Autodesk Fusion 360 part; units mm, degrees
(part 2 of 4)
sketch "Switch_Latch" plane through (0, 0, 0) normal (0, 0, -1) x (1, 0, 0) in component "Plate_Left"
  line L0 (111.75, 39.3) -> (111.75, 25.3)
  line L1 (111.75, 25.3) -> (97.75, 25.3)
  line L2 (97.75, 25.3) -> (97.75, 39.3)
  line L3 (97.75, 39.3) -> (111.75, 39.3)
  line L4 (92.7, 55.69) -> (92.7, 41.69)
  line L5 (92.7, 41.69) -> (78.7, 41.69)
  line L6 (78.7, 41.69) -> (78.7, 55.69)
  line L7 (78.7, 55.69) -> (92.7, 55.69)
  line L8 (59.65, 78.7) -> (59.65, 92.7)
  line L9 (59.65, 92.7) -> (73.65, 92.7)
  line L10 (73.65, 92.7) -> (73.65, 78.7)
  line L11 (73.65, 78.7) -> (59.65, 78.7)
  line L12 (59.65, 16.5) -> (73.65, 16.5)
  line L13 (73.65, 16.5) -> (73.65, 2.5)
  line L14 (73.65, 2.5) -> (59.65, 2.5)
  line L15 (59.65, 2.5) -> (59.65, 16.5)
  line L16 (40.6, 79.79) -> (40.6, 93.79)
  line L17 (40.6, 93.79) -> (54.6, 93.79)
  line L18 (54.6, 93.79) -> (54.6, 79.79)
  line L19 (54.6, 79.79) -> (40.6, 79.79)
  line L20 (21.55, 21.21) -> (35.55, 21.21)
  line L21 (35.55, 21.21) -> (35.55, 7.21)
  line L22 (35.55, 7.21) -> (21.55, 7.21)
  line L23 (21.55, 7.21) -> (21.55, 21.21)
  line L24 (2.5, 79.5) -> (16.5, 79.5)
  line L25 (16.5, 79.5) -> (16.5, 65.5)
  line L26 (16.5, 65.5) -> (2.5, 65.5)
  line L27 (2.5, 65.5) -> (2.5, 79.5)
  line L28 (2.5, 98.55) -> (16.5, 98.55)
  line L29 (16.5, 98.55) -> (16.5, 84.55)
  line L30 (16.5, 84.55) -> (2.5, 84.55)
  line L31 (2.5, 84.55) -> (2.5, 98.55)
  line L32 (2.5, 60.45) -> (16.5, 60.45)
  line L33 (16.5, 60.45) -> (16.5, 46.45)
  line L34 (16.5, 46.45) -> (2.5, 46.45)
  line L35 (2.5, 46.45) -> (2.5, 60.45)
  line L36 (35.55, 40.26) -> (35.55, 26.26)
  line L37 (35.55, 26.26) -> (21.55, 26.26)
  line L38 (21.55, 26.26) -> (21.55, 40.26)
  line L39 (21.55, 40.26) -> (35.55, 40.26)
  line L40 (54.6, 55.69) -> (54.6, 41.69)
  line L41 (54.6, 41.69) -> (40.6, 41.69)
  line L42 (40.6, 41.69) -> (40.6, 55.69)
  line L43 (40.6, 55.69) -> (54.6, 55.69)
  line L44 (73.65, 35.55) -> (73.65, 21.55)
  line L45 (73.65, 21.55) -> (59.65, 21.55)
  line L46 (59.65, 21.55) -> (59.65, 35.55)
  line L47 (59.65, 35.55) -> (73.65, 35.55)
  line L48 (90.1617, 83.0445) -> (84.4545, 95.8284)
  line L49 (84.4545, 95.8284) -> (97.2384, 101.5355)
  line L50 (97.2384, 101.5355) -> (102.9456, 88.7516)
  line L51 (102.9456, 88.7516) -> (90.1617, 83.0445)
  line L52 (92.7, 36.64) -> (92.7, 22.64)
  line L53 (92.7, 22.64) -> (78.7, 22.64)
  line L54 (78.7, 22.64) -> (78.7, 36.64)
  line L55 (78.7, 36.64) -> (92.7, 36.64)
  line L56 (111.75, 58.35) -> (111.75, 44.35)
  line L57 (111.75, 44.35) -> (97.75, 44.35)
  line L58 (97.75, 44.35) -> (97.75, 58.35)
  line L59 (97.75, 58.35) -> (111.75, 58.35)
  line L60 (97.75, 20.25) -> (111.75, 20.25)
  line L61 (111.75, 20.25) -> (111.75, 6.25)
  line L62 (111.75, 6.25) -> (97.75, 6.25)
  line L63 (97.75, 6.25) -> (97.75, 20.25)
  line L64 (78.7, 60.74) -> (78.7, 74.74)
  line L65 (78.7, 74.74) -> (92.7, 74.74)
  line L66 (92.7, 74.74) -> (92.7, 60.74)
  line L67 (92.7, 60.74) -> (78.7, 60.74)
  line L68 (59.65, 59.65) -> (59.65, 73.65)
  line L69 (59.65, 73.65) -> (73.65, 73.65)
  line L70 (73.65, 73.65) -> (73.65, 59.65)
  line L71 (73.65, 59.65) -> (59.65, 59.65)
  line L72 (40.6, 17.59) -> (54.6, 17.59)
  line L73 (54.6, 17.59) -> (54.6, 3.59)
  line L74 (54.6, 3.59) -> (40.6, 3.59)
  line L75 (40.6, 3.59) -> (40.6, 17.59)
  line L76 (40.6, 60.74) -> (40.6, 74.74)
  line L77 (40.6, 74.74) -> (54.6, 74.74)
  line L78 (54.6, 74.74) -> (54.6, 60.74)
  line L79 (54.6, 60.74) -> (40.6, 60.74)
  line L80 (16.5, 22.35) -> (16.5, 8.35)
  line L81 (16.5, 8.35) -> (2.5, 8.35)
  line L82 (2.5, 8.35) -> (2.5, 22.35)
  line L83 (2.5, 22.35) -> (16.5, 22.35)
  line L84 (21.55, 64.36) -> (21.55, 78.36)
  line L85 (21.55, 78.36) -> (35.55, 78.36)
  line L86 (35.55, 78.36) -> (35.55, 64.36)
  line L87 (35.55, 64.36) -> (21.55, 64.36)
  line L88 (21.55, 83.41) -> (21.55, 97.41)
  line L89 (21.55, 97.41) -> (35.55, 97.41)
  line L90 (35.55, 97.41) -> (35.55, 83.41)
  line L91 (35.55, 83.41) -> (21.55, 83.41)
  line L92 (2.5, 27.4) -> (2.5, 41.4)
  line L93 (2.5, 41.4) -> (16.5, 41.4)
  line L94 (16.5, 41.4) -> (16.5, 27.4)
  line L95 (16.5, 27.4) -> (2.5, 27.4)
  line L96 (35.55, 59.31) -> (35.55, 45.31)
  line L97 (35.55, 45.31) -> (21.55, 45.31)
  line L98 (21.55, 45.31) -> (21.55, 59.31)
  line L99 (21.55, 59.31) -> (35.55, 59.31)
  line L100 (54.6, 36.64) -> (54.6, 22.64)
  line L101 (54.6, 22.64) -> (40.6, 22.64)
  line L102 (40.6, 22.64) -> (40.6, 36.64)
  line L103 (40.6, 36.64) -> (54.6, 36.64)
  line L104 (73.65, 54.6) -> (73.65, 40.6)
  line L105 (73.65, 40.6) -> (59.65, 40.6)
  line L106 (59.65, 40.6) -> (59.65, 54.6)
  line L107 (59.65, 54.6) -> (73.65, 54.6)
  line L108 (112.7117, 92.7045) -> (107.0045, 105.4884)
  line L109 (107.0045, 105.4884) -> (119.7884, 111.1955)
  line L110 (119.7884, 111.1955) -> (125.4956, 98.4116)
  line L111 (125.4956, 98.4116) -> (112.7117, 92.7045)
  line L112 (78.7, 17.59) -> (92.7, 17.59)
  line L113 (92.7, 17.59) -> (92.7, 3.59)
  line L114 (92.7, 3.59) -> (78.7, 3.59)
  line L115 (78.7, 3.59) -> (78.7, 17.59)
  line L116 (97.75, 63.4) -> (97.75, 77.4)
  line L117 (97.75, 77.4) -> (111.75, 77.4)
  line L118 (111.75, 77.4) -> (111.75, 63.4)
  line L119 (111.75, 63.4) -> (97.75, 63.4)
  line L120 (119.3123, 118.9999) -> (83.6581, 103.172)
  arc A0 (82.8467, 103) -> (83.6581, 103.172) centre (82.8467, 105) ccw
  line L121 (82.8467, 103) -> (0, 103)
  arc A1 (0, 103) -> (-6, 97) centre (0, 97) ccw
  line L122 (-6, 97) -> (-6, 6.0028)
  arc A2 (-6, 6.0028) -> (0, 0.0028) centre (0, 6.0028) ccw
  line L123 (0, 0.0028) -> (135.25, 0.0028)
  arc A3 (135.25, 0.0028) -> (141.25, 6.0028) centre (135.25, 6.0028) ccw
  line L124 (141.25, 6.0028) -> (141.25, 113.172)
  arc A4 (141.25, 113.172) -> (135.25, 119.172) centre (135.25, 113.172) ccw
  line L125 (135.25, 119.172) -> (120.1238, 119.172)
  arc A5 (120.1238, 119.172) -> (119.3123, 118.9999) centre (120.1238, 117.172) ccw
  line L126 (107.75, 20.25) -> (101.75, 20.25)
  line L127 (101.75, 20.25) -> (101.75, 21.75)
  line L128 (101.75, 21.75) -> (107.75, 21.75)
  line L129 (107.75, 21.75) -> (107.75, 20.25)
  line L130 (107.75, 4.75) -> (101.75, 4.75)
  line L131 (101.75, 4.75) -> (101.75, 6.25)
  line L132 (101.75, 6.25) -> (107.75, 6.25)
  line L133 (107.75, 6.25) -> (107.75, 4.75)
  line L134 (101.75, 25.3) -> (107.75, 25.3)
  line L135 (107.75, 25.3) -> (107.75, 23.8)
  line L136 (107.75, 23.8) -> (101.75, 23.8)
  line L137 (101.75, 23.8) -> (101.75, 25.3)
  line L138 (107.75, 39.3) -> (101.75, 39.3)
  line L139 (101.75, 39.3) -> (101.75, 40.8)
  line L140 (107.75, 40.8) -> (107.75, 39.3)
  line L141 (101.75, 40.8) -> (107.75, 40.8)
  line L142 (101.75, 44.35) -> (107.75, 44.35)
  line L143 (101.75, 58.35) -> (101.75, 59.85)
  line L144 (107.75, 44.35) -> (107.75, 42.85)
  line L145 (107.75, 59.85) -> (107.75, 58.35)
  line L146 (101.75, 42.85) -> (101.75, 44.35)
  line L147 (107.75, 42.85) -> (101.75, 42.85)
  line L148 (107.75, 58.35) -> (101.75, 58.35)
  line L149 (101.75, 59.85) -> (107.75, 59.85)
  line L150 (88.7, 21.14) -> (82.7, 21.14)
  line L151 (88.7, 3.59) -> (88.7, 2.09)
  line L152 (82.7, 2.09) -> (82.7, 3.59)
  line L153 (88.7, 17.59) -> (82.7, 17.59)
  line L154 (88.7, 2.09) -> (82.7, 2.09)
  line L155 (88.7, 22.64) -> (88.7, 21.14)
  line L156 (82.7, 21.14) -> (82.7, 22.64)
  line L157 (88.7, 38.14) -> (88.7, 36.64)
  line L158 (82.7, 19.09) -> (88.7, 19.09)
  line L159 (82.7, 36.64) -> (82.7, 38.14)
  line L160 (82.7, 22.64) -> (88.7, 22.64)
  line L161 (88.7, 36.64) -> (82.7, 36.64)
  line L162 (82.7, 17.59) -> (82.7, 19.09)
  line L163 (82.7, 38.14) -> (88.7, 38.14)
  line L164 (88.7, 19.09) -> (88.7, 17.59)
  line L165 (82.7, 3.59) -> (88.7, 3.59)
  line L166 (88.7, 41.69) -> (88.7, 40.19)
  line L167 (101.75, 61.9) -> (101.75, 63.4)
  line L168 (88.7, 57.19) -> (88.7, 55.69)
  line L169 (82.7, 57.19) -> (88.7, 57.19)
  line L170 (82.7, 55.69) -> (82.7, 57.19)
  line L171 (88.7, 55.69) -> (82.7, 55.69)
  line L172 (101.75, 78.9) -> (107.75, 78.9)
  line L173 (107.75, 78.9) -> (107.75, 77.4)
  line L174 (88.7, 40.19) -> (82.7, 40.19)
  line L175 (82.7, 40.19) -> (82.7, 41.69)
  line L176 (107.75, 61.9) -> (101.75, 61.9)
  line L177 (101.75, 77.4) -> (101.75, 78.9)
  line L178 (107.75, 77.4) -> (101.75, 77.4)
  line L179 (101.75, 63.4) -> (107.75, 63.4)
  line L180 (82.7, 41.69) -> (88.7, 41.69)
  line L181 (107.75, 63.4) -> (107.75, 61.9)
  line L182 (88.7, 60.74) -> (88.7, 59.24)
  line L183 (88.7, 59.24) -> (82.7, 59.24)
  line L184 (82.7, 60.74) -> (88.7, 60.74)
  line L185 (88.7, 74.74) -> (82.7, 74.74)
  line L186 (82.7, 76.24) -> (88.7, 76.24)
  line L187 (82.7, 59.24) -> (82.7, 60.74)
  line L188 (88.7, 76.24) -> (88.7, 74.74)
  line L189 (82.7, 74.74) -> (82.7, 76.24)
  line L190 (69.65, 77.2) -> (63.65, 77.2)
  line L191 (69.65, 73.65) -> (63.65, 73.65)
  line L192 (63.65, 59.65) -> (69.65, 59.65)
  line L193 (63.65, 78.7) -> (69.65, 78.7)
  line L194 (69.65, 58.15) -> (63.65, 58.15)
  line L195 (63.65, 92.7) -> (63.65, 94.2)
  line L196 (69.65, 92.7) -> (63.65, 92.7)
  line L197 (63.65, 77.2) -> (63.65, 78.7)
  line L198 (69.65, 75.15) -> (69.65, 73.65)
  line L199 (63.65, 73.65) -> (63.65, 75.15)
  line L200 (63.65, 75.15) -> (69.65, 75.15)
  line L201 (69.65, 78.7) -> (69.65, 77.2)
  line L202 (63.65, 94.2) -> (69.65, 94.2)
  line L203 (69.65, 59.65) -> (69.65, 58.15)
  line L204 (63.65, 58.15) -> (63.65, 59.65)
  line L205 (69.65, 94.2) -> (69.65, 92.7)
  line L206 (50.6, 95.29) -> (50.6, 93.79)
  line L207 (31.55, 98.91) -> (31.55, 97.41)
  line L208 (50.6, 79.79) -> (50.6, 78.29)
  line L209 (44.6, 38.14) -> (50.6, 38.14)
  line L210 (44.6, 93.79) -> (44.6, 95.29)
  line L211 (25.55, 83.41) -> (31.55, 83.41)
  line L212 (50.6, 21.14) -> (44.6, 21.14)
  line L213 (31.55, 81.91) -> (25.55, 81.91)
  line L214 (50.6, 36.64) -> (44.6, 36.64)
  line L215 (44.6, 21.14) -> (44.6, 22.64)
  line L216 (6.5, 98.55) -> (6.5, 100.05)
  line L217 (12.5, 100.05) -> (12.5, 98.55)
  line L218 (44.6, 36.64) -> (44.6, 38.14)
  line L219 (44.6, 79.79) -> (50.6, 79.79)
  line L220 (44.6, 22.64) -> (50.6, 22.64)
  line L221 (50.6, 93.79) -> (44.6, 93.79)
  line L222 (44.6, 78.29) -> (44.6, 79.79)
  line L223 (6.5, 100.05) -> (12.5, 100.05)
  line L224 (50.6, 78.29) -> (44.6, 78.29)
  line L225 (12.5, 83.05) -> (6.5, 83.05)
  line L226 (50.6, 22.64) -> (50.6, 21.14)
  line L227 (12.5, 84.55) -> (12.5, 83.05)
  line L228 (6.5, 84.55) -> (12.5, 84.55)
  line L229 (44.6, 95.29) -> (50.6, 95.29)
  line L230 (6.5, 83.05) -> (6.5, 84.55)
  line L231 (50.6, 38.14) -> (50.6, 36.64)
  line L232 (31.55, 97.41) -> (25.55, 97.41)
  line L233 (12.5, 98.55) -> (6.5, 98.55)
  line L234 (31.55, 83.41) -> (31.55, 81.91)
  line L235 (25.55, 98.91) -> (31.55, 98.91)
  line L236 (25.55, 81.91) -> (25.55, 83.41)
  line L237 (25.55, 97.41) -> (25.55, 98.91)
  line L238 (31.55, 62.86) -> (25.55, 62.86)
  line L239 (69.65, 35.55) -> (63.65, 35.55)
  line L240 (50.6, 41.69) -> (50.6, 40.19)
  line L241 (50.6, 40.19) -> (44.6, 40.19)
  line L242 (69.65, 20.05) -> (63.65, 20.05)
  line L243 (63.65, 40.6) -> (69.65, 40.6)
  line L244 (31.55, 59.31) -> (25.55, 59.31)
  line L245 (6.5, 65.5) -> (12.5, 65.5)
  line L246 (25.55, 45.31) -> (31.55, 45.31)
  line L247 (12.5, 64) -> (6.5, 64)
  line L248 (69.65, 54.6) -> (63.65, 54.6)
  line L249 (69.65, 40.6) -> (69.65, 39.1)
  line L250 (12.5, 46.45) -> (12.5, 44.95)
  line L251 (6.5, 79.5) -> (6.5, 81)
  line L252 (31.55, 64.36) -> (31.55, 62.86)
  line L253 (44.6, 40.19) -> (44.6, 41.69)
  line L254 (12.5, 60.45) -> (6.5, 60.45)
  line L255 (31.55, 78.36) -> (25.55, 78.36)
  line L256 (44.6, 76.24) -> (50.6, 76.24)
  line L257 (50.6, 55.69) -> (44.6, 55.69)
  line L258 (63.65, 20.05) -> (63.65, 21.55)
  line L259 (50.6, 74.74) -> (44.6, 74.74)
  line L260 (44.6, 41.69) -> (50.6, 41.69)
  line L261 (63.65, 56.1) -> (69.65, 56.1)
  line L262 (6.5, 64) -> (6.5, 65.5)
  line L263 (69.65, 56.1) -> (69.65, 54.6)
  line L264 (12.5, 81) -> (12.5, 79.5)
  line L265 (63.65, 21.55) -> (69.65, 21.55)
  line L266 (44.6, 59.24) -> (44.6, 60.74)
  line L267 (50.6, 60.74) -> (50.6, 59.24)
  line L268 (6.5, 44.95) -> (6.5, 46.45)
  line L269 (69.65, 39.1) -> (63.65, 39.1)
  line L270 (44.6, 60.74) -> (50.6, 60.74)
  line L271 (31.55, 43.81) -> (25.55, 43.81)
  line L272 (12.5, 61.95) -> (12.5, 60.45)
  line L273 (25.55, 43.81) -> (25.55, 45.31)
  line L274 (69.65, 21.55) -> (69.65, 20.05)
  line L275 (25.55, 64.36) -> (31.55, 64.36)
  line L276 (12.5, 79.5) -> (6.5, 79.5)
  line L277 (6.5, 46.45) -> (12.5, 46.45)
  line L278 (6.5, 60.45) -> (6.5, 61.95)
  line L279 (12.5, 44.95) -> (6.5, 44.95)
  line L280 (63.65, 39.1) -> (63.65, 40.6)
  line L281 (25.55, 62.86) -> (25.55, 64.36)
  line L282 (12.5, 65.5) -> (12.5, 64)
  line L283 (6.5, 61.95) -> (12.5, 61.95)
  line L284 (50.6, 76.24) -> (50.6, 74.74)
  line L285 (25.55, 59.31) -> (25.55, 60.81)
  line L286 (44.6, 74.74) -> (44.6, 76.24)
  line L287 (44.6, 55.69) -> (44.6, 57.19)
  line L288 (63.65, 54.6) -> (63.65, 56.1)
  line L289 (31.55, 45.31) -> (31.55, 43.81)
  line L290 (6.5, 81) -> (12.5, 81)
  line L291 (50.6, 59.24) -> (44.6, 59.24)
  line L292 (63.65, 37.05) -> (69.65, 37.05)
  line L293 (25.55, 60.81) -> (31.55, 60.81)
  line L294 (69.65, 37.05) -> (69.65, 35.55)
  line L295 (25.55, 79.86) -> (31.55, 79.86)
  line L296 (31.55, 79.86) -> (31.55, 78.36)
  line L297 (50.6, 57.19) -> (50.6, 55.69)
  line L298 (44.6, 57.19) -> (50.6, 57.19)
  line L299 (25.55, 78.36) -> (25.55, 79.86)
  line L300 (63.65, 35.55) -> (63.65, 37.05)
  line L301 (31.55, 60.81) -> (31.55, 59.31)
  line L302 (12.5, 41.4) -> (6.5, 41.4)
  line L303 (12.5, 25.9) -> (6.5, 25.9)
  line L304 (25.55, 26.26) -> (31.55, 26.26)
  line L305 (69.65, 16.5) -> (63.65, 16.5)
  line L306 (25.55, 7.21) -> (31.55, 7.21)
  line L307 (63.65, 2.5) -> (69.65, 2.5)
  line L308 (31.55, 5.71) -> (25.55, 5.71)
  line L309 (31.55, 40.26) -> (25.55, 40.26)
  line L310 (31.55, 26.26) -> (31.55, 24.76)
  line L311 (50.6, 3.59) -> (50.6, 2.09)
  line L312 (25.55, 21.21) -> (25.55, 22.71)
  line L313 (50.6, 17.59) -> (44.6, 17.59)
  line L314 (6.5, 23.85) -> (12.5, 23.85)
  line L315 (6.5, 25.9) -> (6.5, 27.4)
  line L316 (12.5, 22.35) -> (6.5, 22.35)
  line L317 (25.55, 41.76) -> (31.55, 41.76)
  line L318 (25.55, 5.71) -> (25.55, 7.21)
  line L319 (31.55, 41.76) -> (31.55, 40.26)
  line L320 (31.55, 22.71) -> (31.55, 21.21)
  line L321 (6.5, 27.4) -> (12.5, 27.4)
  line L322 (6.5, 6.85) -> (6.5, 8.35)
  line L323 (12.5, 8.35) -> (12.5, 6.85)
  line L324 (44.6, 2.09) -> (44.6, 3.59)
  line L325 (31.55, 24.76) -> (25.55, 24.76)
  line L326 (6.5, 8.35) -> (12.5, 8.35)
  line L327 (69.65, 1) -> (63.65, 1)
  line L328 (50.6, 19.09) -> (50.6, 17.59)
  line L329 (63.65, 1) -> (63.65, 2.5)
  line L330 (12.5, 27.4) -> (12.5, 25.9)
  line L331 (31.55, 21.21) -> (25.55, 21.21)
  line L332 (44.6, 3.59) -> (50.6, 3.59)
  line L333 (44.6, 17.59) -> (44.6, 19.09)
  line L334 (50.6, 2.09) -> (44.6, 2.09)
  line L335 (25.55, 24.76) -> (25.55, 26.26)
  line L336 (31.55, 7.21) -> (31.55, 5.71)
  line L337 (44.6, 19.09) -> (50.6, 19.09)
  line L338 (12.5, 23.85) -> (12.5, 22.35)
  line L339 (63.65, 16.5) -> (63.65, 18)
  line L340 (6.5, 22.35) -> (6.5, 23.85)
  line L341 (25.55, 40.26) -> (25.55, 41.76)
  line L342 (69.65, 2.5) -> (69.65, 1)
  line L343 (25.55, 22.71) -> (31.55, 22.71)
  line L344 (12.5, 6.85) -> (6.5, 6.85)
  line L345 (6.5, 42.9) -> (12.5, 42.9)
  line L346 (63.65, 18) -> (69.65, 18)
  line L347 (12.5, 42.9) -> (12.5, 41.4)
  line L348 (6.5, 41.4) -> (6.5, 42.9)
  line L349 (69.65, 18) -> (69.65, 16.5)
  line L350 (93.5858, 99.9049) -> (88.107, 97.459)
  line L351 (88.107, 97.459) -> (87.4955, 98.8287)
  line L352 (87.4955, 98.8287) -> (92.9744, 101.2746)
  line L353 (92.9744, 101.2746) -> (93.5858, 99.9049)
  line L354 (93.8142, 84.6751) -> (99.293, 87.121)
  line L355 (99.293, 87.121) -> (99.9045, 85.7513)
  line L356 (99.9045, 85.7513) -> (94.4257, 83.3054)
  line L357 (94.4257, 83.3054) -> (93.8142, 84.6751)
  line L358 (116.1358, 109.5649) -> (110.657, 107.119)
  line L359 (110.657, 107.119) -> (110.0455, 108.4887)
  line L360 (110.0455, 108.4887) -> (115.5244, 110.9346)
  line L361 (115.5244, 110.9346) -> (116.1358, 109.5649)
  line L362 (122.4545, 95.4113) -> (116.9757, 92.9654)
  line L363 (116.9757, 92.9654) -> (116.3642, 94.3351)
  line L364 (121.843, 96.781) -> (122.4545, 95.4113)
  line L365 (116.3642, 94.3351) -> (121.843, 96.781)
  point P0 (104.75, 20.25)
  point P1 (104.75, 6.25)
  point P2 (104.75, 25.3)
  point P3 (104.75, 39.3)
  point P4 (104.75, 44.35)
  point P5 (104.75, 58.35)
  point P6 (85.7, 3.59)
  point P7 (85.7, 17.59)
  point P8 (85.7, 22.64)
  point P9 (85.7, 36.64)
  point P10 (85.7, 41.69)
  point P11 (85.7, 55.69)
  point P12 (104.75, 63.4)
  point P13 (104.75, 77.4)
  point P14 (85.7, 60.74)
  point P15 (85.7, 74.74)
  point P16 (66.65, 78.7)
  point P17 (66.65, 73.65)
  point P18 (66.65, 59.65)
  point P19 (66.65, 92.7)
  point P20 (47.6, 22.64)
  point P21 (9.5, 98.55)
  point P22 (9.5, 84.55)
  point P23 (47.6, 36.64)
  point P24 (28.55, 83.41)
  point P25 (47.6, 93.79)
  point P26 (28.55, 97.41)
  point P27 (47.6, 79.79)
  point P28 (9.5, 46.45)
  point P29 (9.5, 79.5)
  point P30 (9.5, 65.5)
  point P31 (9.5, 60.45)
  point P32 (47.6, 60.74)
  point P33 (66.65, 54.6)
  point P34 (47.6, 74.74)
  point P35 (66.65, 40.6)
  point P36 (28.55, 64.36)
  point P37 (47.6, 41.69)
  point P38 (28.55, 45.31)
  point P39 (47.6, 55.69)
  point P40 (28.55, 59.31)
  point P41 (66.65, 35.55)
  point P42 (28.55, 78.36)
  point P43 (66.65, 21.55)
  point P44 (47.6, 3.59)
  point P45 (28.55, 21.21)
  point P46 (28.55, 7.21)
  point P47 (47.6, 17.59)
  point P48 (9.5, 8.35)
  point P49 (28.55, 40.26)
  point P50 (9.5, 22.35)
  point P51 (28.55, 26.26)
  point P52 (66.65, 2.5)
  point P53 (66.65, 16.5)
  point P54 (9.5, 41.4)
  point P55 (9.5, 27.4)
  point P56 (96.5536, 85.898)
  point P57 (90.8464, 98.682)
  point P58 (119.1036, 95.558)
  point P59 (113.3964, 108.342)
  dimension "d236" = 6
  dimension "d237" = 1.5
  dimension "d238" = 6
  dimension "d239" = 1.5
  dimension "d240" = 6
  dimension "d241" = 1.5
  dimension "d242" = 6
  dimension "d243" = 1.5
  dimension "d244" = 6
  dimension "d245" = 1.5
  dimension "d246" = 6
  dimension "d247" = 1.5
  dimension "d248" = 6
  dimension "d249" = 1.5
  dimension "d250" = 6
  dimension "d251" = 1.5
  dimension "d252" = 6
  dimension "d253" = 1.5
  dimension "d254" = 6
  dimension "d255" = 1.5
  dimension "d256" = 6
  dimension "d257" = 1.5
  dimension "d258" = 6
  dimension "d259" = 1.5
  dimension "d264" = 6
  dimension "d265" = 1.5
  dimension "d266" = 6
  dimension "d267" = 1.5
  dimension "d326" = 6
  dimension "d327" = 1.5
  dimension "d328" = 6
  dimension "d329" = 1.5
  dimension "d330" = 6
  dimension "d331" = 1.5
  dimension "d332" = 6
  dimension "d333" = 1.5
  dimension "d334" = 6
  dimension "d335" = 1.5
  dimension "d336" = 6
  dimension "d337" = 1.5
  dimension "d338" = 6
  dimension "d339" = 1.5
  dimension "d340" = 6
  dimension "d341" = 1.5
  dimension "d342" = 6
  dimension "d343" = 1.5
  dimension "d344" = 6
  dimension "d345" = 1.5
  dimension "d346" = 6
  dimension "d347" = 1.5
  dimension "d348" = 6
  dimension "d349" = 1.5
  dimension "d350" = 6
  dimension "d351" = 1.5
  dimension "d352" = 6
  dimension "d353" = 1.5
  dimension "d354" = 6
  dimension "d355" = 1.5
  dimension "d356" = 6
  dimension "d357" = 1.5
  dimension "d358" = 6
  dimension "d359" = 1.5
  dimension "d360" = 6
  dimension "d361" = 1.5
  dimension "d362" = 6
  dimension "d363" = 1.5
  dimension "d364" = 6
  dimension "d365" = 1.5
  dimension "d366" = 6
  dimension "d367" = 1.5
  dimension "d368" = 6
  dimension "d369" = 1.5
  dimension "d370" = 6
  dimension "d371" = 1.5
  dimension "d372" = 6
  dimension "d373" = 1.5
  dimension "d374" = 6
  dimension "d375" = 1.5
  dimension "d376" = 6
  dimension "d377" = 1.5
  dimension "d378" = 6
  dimension "d379" = 1.5
  dimension "d380" = 6
  dimension "d381" = 1.5
  dimension "d382" = 6
  dimension "d383" = 1.5
  dimension "d384" = 6
  dimension "d385" = 1.5
  dimension "d386" = 6
  dimension "d387" = 1.5
  dimension "d388" = 6
  dimension "d389" = 1.5
  dimension "d390" = 6
  dimension "d391" = 1.5
  dimension "d392" = 6
  dimension "d393" = 1.5
  dimension "d394" = 6
  dimension "d395" = 1.5
  dimension "d396" = 6
  dimension "d397" = 1.5
  dimension "d398" = 6
  dimension "d399" = 1.5
  dimension "d400" = 6
  dimension "d401" = 1.5
  dimension "d402" = 6
  dimension "d403" = 1.5
  dimension "d404" = 6
  dimension "d405" = 1.5
  dimension "d414" = 6
  dimension "d415" = 1.5
  dimension "d416" = 6
  dimension "d417" = 1.5
  dimension "d418" = 6
  dimension "d419" = 1.5
  dimension "d420" = 6
  dimension "d421" = 1.5
  dimension "d422" = 6
  dimension "d423" = 1.5
  dimension "d424" = 6
  dimension "d425" = 1.5
  constraint horizontal L126
  constraint vertical L127
  constraint horizontal L128
  constraint vertical L129
  constraint midpoint L126 P0
  constraint midpoint L60 P0
  constraint horizontal L130
  constraint vertical L131
  constraint horizontal L132
  constraint vertical L133
  constraint midpoint L132 P1
  constraint midpoint L62 P1
  constraint horizontal L138
  constraint vertical L139
  constraint horizontal L141
  constraint vertical L140
  constraint midpoint P3 L138
  constraint horizontal L136
  constraint vertical L137
  constraint horizontal L134
  constraint vertical L135
  constraint midpoint P2 L134
  constraint horizontal L148
  constraint vertical L143
  constraint horizontal L149
  constraint vertical L145
  constraint midpoint P5 L148
  constraint horizontal L147
  constraint vertical L146
  constraint horizontal L142
  constraint vertical L144
  constraint midpoint P4 L142
  constraint horizontal L153
  constraint vertical L162
  constraint horizontal L158
  constraint vertical L164
  constraint midpoint P7 L153
  constraint horizontal L154
  constraint vertical L152
  constraint horizontal L165
  constraint vertical L151
  constraint midpoint P6 L165
  constraint horizontal L161
  constraint vertical L159
  constraint horizontal L163
  constraint vertical L157
  constraint midpoint P9 L161
  constraint horizontal L150
  constraint vertical L156
  constraint horizontal L160
  constraint vertical L155
  constraint midpoint P8 L160
  constraint horizontal L171
  constraint vertical L170
  constraint horizontal L169
  constraint vertical L168
  constraint midpoint P11 L171
  constraint horizontal L174
  constraint vertical L175
  constraint horizontal L180
  constraint vertical L166
  constraint midpoint P10 L180
  constraint horizontal L178
  constraint vertical L177
  constraint horizontal L172
  constraint vertical L173
  constraint midpoint P13 L178
  constraint horizontal L176
  constraint vertical L167
  constraint horizontal L179
  constraint vertical L181
  constraint midpoint P12 L179
  constraint midpoint L1 P2
  constraint midpoint L3 P3
  constraint midpoint L57 P4
  constraint midpoint L59 P5
  constraint midpoint L114 P6
  constraint midpoint L53 P8
  constraint midpoint L112 P7
  constraint midpoint L55 P9
  constraint midpoint L5 P10
  constraint midpoint L7 P11
  constraint horizontal L185
  constraint vertical L189
  constraint horizontal L186
  constraint vertical L188
  constraint midpoint P15 L185
  constraint horizontal L183
  constraint vertical L187
  constraint horizontal L184
  constraint vertical L182
  constraint midpoint P14 L184
  constraint horizontal L196
  constraint vertical L195
  constraint horizontal L202
  constraint vertical L205
  constraint midpoint P19 L196
  constraint horizontal L190
  constraint vertical L197
  constraint horizontal L193
  constraint vertical L201
  constraint midpoint P16 L193
  constraint horizontal L191
  constraint vertical L199
  constraint horizontal L200
  constraint vertical L198
  constraint midpoint P17 L191
  constraint horizontal L194
  constraint vertical L204
  constraint horizontal L192
  constraint vertical L203
  constraint midpoint P18 L192
  constraint horizontal L214
  constraint vertical L218
  constraint horizontal L209
  constraint vertical L231
  constraint midpoint P23 L214
  constraint horizontal L212
  constraint vertical L215
  constraint horizontal L220
  constraint vertical L226
  constraint midpoint P20 L220
  constraint horizontal L233
  constraint vertical L216
  constraint horizontal L223
  constraint vertical L217
  constraint midpoint P21 L233
  constraint horizontal L225
  constraint vertical L230
  constraint horizontal L228
  constraint vertical L227
  constraint midpoint P22 L228
  constraint horizontal L232
  constraint vertical L237
  constraint horizontal L235
  constraint vertical L207
  constraint midpoint P26 L232
  constraint horizontal L213
  constraint vertical L236
  constraint horizontal L211
  constraint vertical L234
  constraint midpoint P24 L211
  constraint horizontal L221
  constraint vertical L210
  constraint horizontal L229
  constraint vertical L206
  constraint midpoint P25 L221
  constraint horizontal L224
  constraint vertical L222
  constraint horizontal L219
  constraint vertical L208
  constraint midpoint P27 L219
  constraint horizontal L254
  constraint vertical L278
  constraint horizontal L283
  constraint vertical L272
  constraint midpoint P31 L254
  constraint horizontal L279
  constraint vertical L268
  constraint horizontal L277
  constraint vertical L250
  constraint midpoint P28 L277
  constraint horizontal L276
  constraint vertical L251
  constraint horizontal L290
  constraint vertical L264
  constraint midpoint P29 L276
  constraint horizontal L247
  constraint vertical L262
  constraint horizontal L245
  constraint vertical L282
  constraint midpoint P30 L245
  constraint horizontal L259
  constraint vertical L286
  constraint horizontal L256
  constraint vertical L284
  constraint midpoint P34 L259
  constraint horizontal L291
  constraint vertical L266
  constraint horizontal L270
  constraint vertical L267
  constraint midpoint P32 L270
  constraint horizontal L248
  constraint vertical L288
  constraint horizontal L261
  constraint vertical L263
  constraint midpoint P33 L248
  constraint horizontal L269
  constraint vertical L280
  constraint horizontal L243
  constraint vertical L249
  constraint midpoint P35 L243
  constraint horizontal L244
  constraint vertical L285
  constraint horizontal L293
  constraint vertical L301
  constraint midpoint P40 L244
  constraint horizontal L271
  constraint vertical L273
  constraint horizontal L246
  constraint vertical L289
  constraint midpoint P38 L246
  constraint horizontal L257
  constraint vertical L287
  constraint horizontal L298
  constraint vertical L297
  constraint midpoint P39 L257
  constraint horizontal L241
  constraint vertical L253
  constraint horizontal L260
  constraint vertical L240
  constraint midpoint P37 L260
  constraint horizontal L255
  constraint vertical L299
  constraint horizontal L295
  constraint vertical L296
  constraint midpoint P42 L255
  constraint horizontal L238
  constraint vertical L281
  constraint horizontal L275
  constraint vertical L252
  constraint midpoint P36 L275
  constraint horizontal L239
  constraint vertical L300
  constraint horizontal L292
  constraint vertical L294
  constraint midpoint P41 L239
  constraint horizontal L242
  constraint vertical L258
  constraint horizontal L265
  constraint vertical L274
  constraint midpoint P43 L265
  constraint midpoint L119 P12
  constraint midpoint L117 P13
  constraint midpoint L67 P14
  constraint midpoint L65 P15
  constraint midpoint L11 P16
  constraint midpoint L71 P18
  constraint midpoint L69 P17
  constraint midpoint L9 P19
  constraint midpoint L19 P27
  constraint midpoint L91 P24
  constraint midpoint L30 P22
  constraint midpoint L17 P25
  constraint midpoint L89 P26
  constraint midpoint L28 P21
  constraint midpoint L105 P35
  constraint midpoint L107 P33
  constraint midpoint L45 P43
  constraint midpoint L47 P41
  constraint midpoint L79 P32
  constraint midpoint L77 P34
  constraint midpoint L87 P36
  constraint midpoint L85 P42
  constraint midpoint L26 P30
  constraint midpoint L24 P29
  constraint midpoint L41 P37
  constraint midpoint L43 P39
  constraint midpoint L99 P40
  constraint midpoint L97 P38
  constraint midpoint L32 P31
  constraint midpoint L34 P28
  constraint midpoint L103 P23
  constraint midpoint L101 P20
  constraint horizontal L313
  constraint vertical L333
  constraint horizontal L337
  constraint vertical L328
  constraint midpoint P47 L313
  constraint horizontal L334
  constraint vertical L324
  constraint horizontal L332
  constraint vertical L311
  constraint midpoint P44 L332
  constraint horizontal L331
  constraint vertical L312
  constraint horizontal L343
  constraint vertical L320
  constraint midpoint P45 L331
  constraint horizontal L308
  constraint vertical L318
  constraint horizontal L306
  constraint vertical L336
  constraint midpoint P46 L306
  constraint horizontal L316
  constraint vertical L340
  constraint horizontal L314
  constraint vertical L338
  constraint midpoint P50 L316
  constraint horizontal L344
  constraint vertical L322
  constraint horizontal L326
  constraint vertical L323
  constraint midpoint P48 L326
  constraint horizontal L309
  constraint vertical L341
  constraint horizontal L317
  constraint vertical L319
  constraint midpoint P49 L309
  constraint horizontal L325
  constraint vertical L335
  constraint horizontal L304
  constraint vertical L310
  constraint midpoint P51 L304
  constraint horizontal L305
  constraint vertical L339
  constraint horizontal L346
  constraint vertical L349
  constraint midpoint P53 L305
  constraint horizontal L327
  constraint vertical L329
  constraint horizontal L307
  constraint vertical L342
  constraint midpoint P52 L307
  constraint horizontal L302
  constraint vertical L348
  constraint horizontal L345
  constraint vertical L347
  constraint midpoint P54 L302
  constraint horizontal L303
  constraint vertical L315
  constraint horizontal L321
  constraint vertical L330
  constraint midpoint P55 L321
  constraint midpoint L14 P52
  constraint midpoint L12 P53
  constraint midpoint L74 P44
  constraint midpoint L72 P47
  constraint midpoint L22 P46
  constraint midpoint L20 P45
  constraint midpoint L37 P51
  constraint midpoint L39 P49
  constraint midpoint L81 P48
  constraint midpoint L83 P50
  constraint midpoint L95 P55
  constraint midpoint L93 P54
  constraint midpoint L354 P56
  constraint midpoint L350 P57
  constraint midpoint L365 P58
  constraint midpoint L358 P59
  constraint midpoint L51 P56
  constraint midpoint L49 P57
  constraint midpoint L109 P59
  constraint midpoint L111 P58
  constraint collinear L111 L365
  constraint collinear L51 L354
  constraint collinear L49 L350
  constraint collinear L109 L358
  constraint parallel L362 L365
  constraint parallel L363 L364
  constraint perpendicular L363 L365
  constraint perpendicular L356 L357
  constraint parallel L355 L357
  constraint parallel L354 L356
  constraint parallel L350 L352
  constraint parallel L351 L353
  constraint parallel L359 L361
  constraint parallel L358 L360
  constraint perpendicular L359 L360
  constraint perpendicular L351 L352
  measures "d236" distance of L126.start L126.end
  measures "d237" distance of L126.start L128.end
  measures "d238" distance of L130.end L130.start
  measures "d239" distance of L130.start L132.end
  measures "d240" distance of L138.end L138.start
  measures "d241" distance of L138.start L140.start
  measures "d242" distance of L136.end L135.end
  measures "d243" distance of L134.end L135.end
  measures "d244" distance of L145.end L143.start
  measures "d245" distance of L145.start L145.end
  measures "d246" distance of L146.start L144.end
  measures "d247" distance of L142.end L144.end
  measures "d248" distance of L153.start L153.end
  measures "d249" distance of L158.end L153.start
  measures "d250" distance of L152.start L151.end
  measures "d251" distance of L151.start L151.end
  measures "d252" distance of L157.end L159.start
  measures "d253" distance of L157.end L157.start
  measures "d254" distance of L150.end L150.start
  measures "d255" distance of L155.start L150.start
  measures "d256" distance of L168.end L170.start
  measures "d257" distance of L168.start L168.end
  measures "d258" distance of L174.end L166.end
  measures "d259" distance of L166.start L166.end
  measures "d264" distance of L177.start L173.end
  measures "d265" distance of L172.end L173.end
  measures "d266" distance of L176.start L167.start
  measures "d267" distance of L179.end L176.start
  measures "d326" distance of L185.end L185.start
  measures "d327" distance of L185.start L186.end
  measures "d328" distance of L182.end L183.end
  measures "d329" distance of L182.start L182.end
  measures "d330" distance of L195.start L196.start
  measures "d331" distance of L196.start L202.end
  measures "d332" distance of L190.start L190.end
  measures "d333" distance of L193.end L190.start
  measures "d334" distance of L191.end L191.start
  measures "d335" distance of L191.start L198.start
  measures "d336" distance of L194.end L194.start
  measures "d337" distance of L192.end L194.start
  measures "d338" distance of L214.end L214.start
  measures "d339" distance of L214.start L209.end
  measures "d340" distance of L212.start L212.end
  measures "d341" distance of L220.end L212.start
  measures "d342" distance of L216.start L217.end
  measures "d343" distance of L217.end L217.start
  measures "d344" distance of L225.end L225.start
  measures "d345" distance of L227.start L225.start
  measures "d346" distance of L207.end L232.end
  measures "d347" distance of L207.end L207.start
  measures "d348" distance of L213.end L213.start
  measures "d349" distance of L211.end L213.start
  measures "d350" distance of L210.start L206.end
  measures "d351" distance of L206.end L206.start
  measures "d352" distance of L222.start L208.end
  measures "d353" distance of L208.start L208.end
  measures "d354" distance of L254.end L254.start
  measures "d355" distance of L254.start L272.start
  measures "d356" distance of L250.end L268.start
  measures "d357" distance of L250.start L250.end
  measures "d358" distance of L251.start L264.end
  measures "d359" distance of L264.end L264.start
  measures "d360" distance of L247.end L247.start
  measures "d361" distance of L245.end L247.start
  measures "d362" distance of L259.start L259.end
  measures "d363" distance of L259.start L256.end
  measures "d364" distance of L266.start L267.end
  measures "d365" distance of L267.start L267.end
  measures "d366" distance of L248.end L248.start
  measures "d367" distance of L248.start L261.end
  measures "d368" distance of L269.end L249.end
  measures "d369" distance of L243.end L249.end
  measures "d370" distance of L244.end L244.start
  measures "d371" distance of L293.end L244.start
  measures "d372" distance of L271.end L271.start
  measures "d373" distance of L271.start L246.end
  measures "d374" distance of L257.end L257.start
  measures "d375" distance of L257.start L297.start
  measures "d376" distance of L241.end L240.end
  measures "d377" distance of L240.start L240.end
  measures "d378" distance of L255.end L255.start
  measures "d379" distance of L295.end L255.start
  measures "d380" distance of L238.end L238.start
  measures "d381" distance of L252.start L238.start
  measures "d382" distance of L239.end L239.start
  measures "d383" distance of L239.start L292.end
  measures "d384" distance of L242.end L242.start
  measures "d385" distance of L265.end L242.start
  measures "d386" distance of L313.end L313.start
  measures "d387" distance of L313.start L328.start
  measures "d388" distance of L311.end L324.start
  measures "d389" distance of L311.start L311.end
  measures "d390" distance of L312.start L320.end
  measures "d391" distance of L320.end L320.start
  measures "d392" distance of L308.end L308.start
  measures "d393" distance of L306.end L308.start
  measures "d394" distance of L316.start L316.end
  measures "d395" distance of L316.start L314.end
  measures "d396" distance of L322.start L323.end
  measures "d397" distance of L323.start L323.end
  measures "d398" distance of L309.end L309.start
  measures "d399" distance of L309.start L317.end
  measures "d400" distance of L325.end L310.end
  measures "d401" distance of L304.end L310.end
  measures "d402" distance of L305.end L305.start
  measures "d403" distance of L346.end L305.start
  measures "d404" distance of L327.end L327.start
  measures "d405" distance of L327.start L307.end
  measures "d414" distance of L302.end L302.start
  measures "d415" distance of L302.start L345.end
  measures "d416" distance of L303.end L303.start
  measures "d417" distance of L321.end L303.start
  measures "d418" distance of L350.start L350.end
  measures "d419" distance of L350.start L352.end
  measures "d420" distance of L356.end L355.end
  measures "d421" distance of L354.end L355.end
  measures "d422" distance of L358.start L358.end
  measures "d423" distance of L358.start L360.end
  measures "d424" distance of L362.end L362.start
  measures "d425" distance of L364.start L362.start
extrude "Extrude7" cut sketch "Switch_Latch" against normal blind 3.6 contours L3 L138 L139 L140 L141 | L1 L134 L135 L136 L137 | L7 L168 L169 L170 L171 | L5 L166 L174 L175 L180 | L11 L190 L193 L197 L201 | L9 L195 L196 L202 L205 | L12 L305 L339 L346 L349 | L14 L307 L327 L329 L342 | L19 L208 L219 L222 L224 | L17 L206 L210 L221 L229 | L20 L312 L320 L331 L343 | L22 L306 L308 L318 L336 | L24 L251 L264 L276 L290 | L26 L245 L247 L262 L282 | L28 L216 L217 L223 L233 | L30 L225 L227 L228 L230 | L32 L254 L272 L278 L283 | L34 L250 L268 L277 L279 | L39 L309 L317 L319 L341 | L37 L304 L310 L325 L335 | L43 L257 L287 L297 L298 | L41 L240 L241 L253 L260 | L47 L239 L292 L294 L300 | L45 L242 L258 L265 L274 | L51 L354 L355 L356 L357 | L49 L350 L351 L352 L353 | L55 L157 L159 L161 L163 | L53 L150 L155 L156 L160 | L59 L143 L145 L148 L149 | L57 L142 L144 L146 L147 | L60 L126 L127 L128 L129 | L62 L130 L131 L132 L133 | L67 L182 L183 L184 L187 | L65 L185 L186 L188 L189 | L71 L192 L194 L203 L204 | L69 L191 L198 L199 L200 | L72 L313 L328 L333 L337 | L74 L311 L324 L332 L334 | L79 L266 L267 L270 L291 | L77 L256 L259 L284 L286 | L83 L314 L316 L338 L340 | L81 L322 L323 L326 L344 | L87 L238 L252 L275 L281 | L85 L255 L295 L296 L299 | L91 L211 L213 L234 L236 | L89 L207 L232 L235 L237 | L95 L303 L315 L321 L330 | L93 L302 L345 L347 L348 | L99 L244 L285 L293 L301 | L97 L246 L271 L273 L289 | L103 L209 L214 L218 L231 | L101 L212 L215 L220 L226 | L107 L248 L261 L263 L288 | L105 L243 L249 L269 L280 | L111 L362 L363 L364 L365 | L109 L358 L359 L360 L361 | L112 L153 L158 L162 L164 | L114 L151 L152 L154 L165 | L119 L167 L176 L179 L181 | L117 L172 L173 L177 L178 bodies 1 in component "Plate_Left"